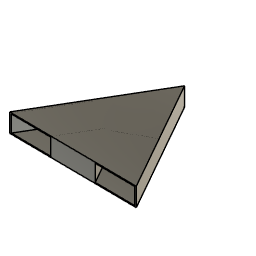
45degreesangle (Autodesk Fusion 360 design; units mm, degrees)
Autodesk Fusion 360 part; units mm, degrees
sketch "Sketch2" plane through (0, 0, 0) normal (0, 0, 1) x (1, 0, 0)
  line L0 (51.6957, -30.4558) -> (0.5277, 59.9977)
  line L1 (0.5277, 59.9977) -> (-52.2234, -29.5419)
  line L2 (-52.2234, -29.5419) -> (51.6957, -30.4558)
extrude "Extrude1" add sketch "Sketch2" along normal blind 15
sketch "Sketch6" plane through (0, 0, 0) normal (0, 0, -1) x (1, 0, 0)
  line L0 (51.6957, 30.4558) -> (-52.2234, 29.5419)
  line L1 (-52.2234, 29.5419) -> (0.5277, -59.9977)
  line L2 (0.5277, -59.9977) -> (51.6957, 30.4558)
  line L3 (-25.9566, -12.7671) -> (0.5074, -57.6869)
  line L4 (0.5074, -57.6869) -> (26.1771, -12.3086)
  line L5 (26.1771, -12.3086) -> (-25.9566, -12.7671)
  line L6 (0.5074, -57.6869) -> (-0.4881, -58.2734)
  line L7 (0.5074, -57.6869) -> (1.513, -58.2558)
  point P0 (0.2426, -27.5875)
  constraint coincident L1 L6.end
  constraint perpendicular L1 L6
  constraint coincident L2 L7.end
  constraint perpendicular L2 L7
extrude "Extrude2" cut sketch "Sketch6" against normal blind 13 contours L3 L4 L5
sketch "Sketch15" plane through (0, 0, 0) normal (0, 0, -1) x (1, 0, 0)
  line L0 (0.5074, -57.6869) -> (-25.9566, -12.7671)
  line L1 (-25.9566, -12.7671) -> (26.1771, -12.3086)
  line L2 (26.1771, -12.3086) -> (0.5074, -57.6869)
  line L3 (51.6957, 30.4558) -> (-52.2234, 29.5419)
  line L4 (-52.2234, 29.5419) -> (0.5277, -59.9977)
  line L5 (0.5277, -59.9977) -> (51.6957, 30.4558)
  line L6 (26.1771, -12.3086) -> (50.3616, 30.4441)
  line L7 (50.3616, 30.4441) -> (25.9907, 44.2303)
  line L8 (25.9907, 44.2303) -> (1.8062, 1.4776)
  line L9 (1.8062, 1.4776) -> (26.1771, -12.3086)
  line L10 (-25.9566, -12.7671) -> (-50.8892, 29.5536)
  line L11 (-50.8892, 29.5536) -> (-26.7646, 43.7663)
  line L12 (-26.7646, 43.7663) -> (-1.8319, 1.4456)
  line L13 (-1.8319, 1.4456) -> (-25.9566, -12.7671)
  dimension "d31" = 28
  dimension "d32" = 28
  constraint perpendicular L6 L7
  constraint parallel L6 L8
  constraint parallel L7 L9
  constraint coincident L3 L6.end
  constraint parallel L2 L6
  constraint coincident L1.end L2.start
  constraint perpendicular L10 L11
  constraint parallel L10 L12
  constraint parallel L11 L13
  constraint coincident L3 L10.end
  constraint parallel L0 L10
  constraint coincident L0.end L1.start
  measures "d31" distance of L1.end L8.end
  measures "d32" distance of L0.end L12.end
extrude "Extrude8" cut sketch "Sketch15" against normal blind 13.5 from surface at -0.75 contours L3 L10 L12 L13 | L3 L6 L8 L9
sketch "Sketch16" plane through (-1.1042, -1.8743, 0) normal (-0.507597, -0.861595, 0) x (0.861595, -0.507597, 0)
  line L0 (-28.8446, 0.75) -> (-0.8446, 0.75)
  line L1 (-0.8446, 0.75) -> (-0.8446, 14.25)
  line L2 (-0.8446, 14.25) -> (-28.8446, 14.25)
  line L3 (-28.8446, 14.25) -> (-28.8446, 13)
  line L4 (-28.8446, 13) -> (-28.8446, 0.75)
  line L5 (-28.8446, 0.75) -> (-0.8446, 0.75)
  line L6 (-0.8446, 0.75) -> (-0.8446, 10.75)
  line L7 (-0.8446, 10.75) -> (-28.8446, 10.75)
  line L8 (-28.8446, 10.75) -> (-28.8446, 0.75)
  dimension "d36" = 10
  constraint horizontal L5
  constraint vertical L6
  constraint horizontal L7
  constraint vertical L8
  constraint coincident L0.start L4.end
  measures "d36" distance of L0.start L7.end
extrude "Extrude9" cut sketch "Sketch16" against normal blind 30 contours L0 L1 L4 L5 L6 L7 L8
sketch "Sketch17" plane through (1.0711, -1.8935, 0) normal (0.492364, -0.870389, 0) x (0.870389, 0.492364, 0)
  line L0 (0.8446, 0.75) -> (28.8446, 0.75)
  line L1 (28.8446, 0.75) -> (28.8446, 13)
  line L2 (28.8446, 13) -> (28.8446, 14.25)
  line L3 (28.8446, 14.25) -> (0.8446, 14.25)
  line L4 (0.8446, 14.25) -> (0.8446, 0.75)
  line L5 (0.8446, 0.75) -> (28.8446, 0.75)
  line L6 (28.8446, 0.75) -> (28.8446, 10.75)
  line L7 (28.8446, 10.75) -> (0.8446, 10.75)
  line L8 (0.8446, 10.75) -> (0.8446, 0.75)
  dimension "d39" = 10
  constraint horizontal L5
  constraint vertical L6
  constraint horizontal L7
  constraint vertical L8
  constraint coincident L0.start L4.end
  measures "d39" distance of L0.start L7.end
extrude "Extrude10" cut sketch "Sketch17" against normal blind 30 contours L0 L1 L4 L5 L6 L7 L8
